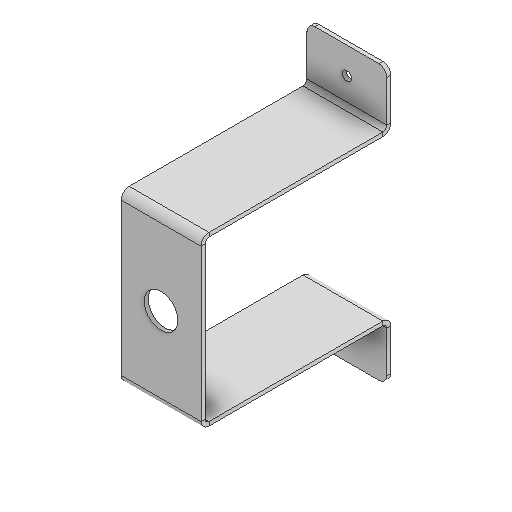
# Autodesk Inventor part: CHAPA 16 DE ACO INOX-304 - SUPORTE CHAVE AUTO-MANUAL
Saved by Autodesk Inventor 2022.2 (Build 262287010, 287A)
## iProperties
Created: 2022-01-21
Part Number: CHAPA 16 DE ACO INOX-304 - SUPORTE CHAVE AUTO-MANUAL
Material: Genérico
Document SubType Name: Sheet Metal
Designer: Projeto
Density: 1 g/cm^3
Flat Pattern Width: 3 cm
Flat Pattern Length: 23.8172 cm
Flat Pattern Area: 71.4515 cm^2
Sheet Metal Rule: Padrão_mm
Sheet Metal Width: 30,000 mm
Sheet Metal Length: 238,172 mm
Sheet Metal Area: 7145,150 mm^2
Appearance: Padrão
Mass: 10.5127 g
Surface Area: 149.083 cm^2
Volume: 10.5127 cm^3
Author: Projeto
Autodesk Inventor part; units mm, degrees
ref_plane "YZ Plane" through (0, 0, 0) normal (1, 0, 0) x (0, 1, 0)
ref_plane "XZ Plane" through (0, 0, 0) normal (0, 1, 0) x (-1, 0, 0)
ref_plane "XY Plane" through (0, 0, 0) normal (0, 0, 1) x (1, 0, 0)
sketch "Esboço1" plane through (0, 0, 0) normal (0, 0, 1) x (1, 0, 0)
  line L0 (15, -30) -> (-15, -30)
  line L1 (-15, -30) -> (-15, 30)
  line L2 (-15, 30) -> (15, 30)
  line L3 (15, 30) -> (15, -30)
  line L4 (15, -30) -> (-15, 30) construction
  line L5 (-15, -30) -> (15, 30) construction
  point P0 (0, 0)
  dimension "d0" = 30
  dimension "d1" = 60
  measures "d0" distance of L1.end L2.end
  measures "d1" distance of L0.end L1.end
extrude "Placa1" add sketch "Esboço1" along normal blind 1.5
sketch "Esboço2" plane through (15, 30, 0) normal (0, 1, 0) x (-1, 0, 0)
  line L0 (30, 0) -> (0, 0)
  line L1 (0, 0) -> (0, -68.3)
  line L2 (0, -68.3) -> (30, -68.3)
  line L3 (30, -68.3) -> (30, 0)
  constraints: 6 end point, 1 horizontal, 1 perpendicular, 1 vertical
edge flange "Flange1" height 68.3 angle 90 thickness 1.5 bend radius 1.5 thickness toward (0, 1, 0) relief tear relief width 1.5 relief depth 0.75 corner gap 1.5 corner form 0 edges at (0, 30, 0) (0, -30, 0) wall of the first edge with corners at (-15, 30, 0) (15, 30, 0) (15, 30, -68.3) (-15, 30, -68.3)
bend "Vergadura1"
corner "Canto1"
sketch "Esboço3" plane through (-15, 31.5, -68.3) normal (0, 0, -1) x (-1, 0, 0)
  line L0 (-30, 0) -> (0, 0)
  line L1 (0, 0) -> (0, 20)
  line L2 (0, 20) -> (-30, 20)
  line L3 (-30, 20) -> (-30, 0)
  constraints: 6 end point, 1 horizontal, 1 perpendicular, 1 vertical
edge flange "Flange2" height 20 angle 90 thickness 1.5 bend radius 1.5 thickness toward (0, 0, -1) relief tear relief width 1.5 relief depth 0.75 corner gap 1.5 corner form 0 edges at (0, 31.5, -68.3) (0, -31.5, -68.3) wall of the first edge with corners at (15, 31.5, -68.3) (-15, 31.5, -68.3) (-15, 51.5, -68.3) (15, 51.5, -68.3)
bend "Vergadura2"
corner "Canto2"
sketch "Esboço4" plane through (15, 51.5, -69.8) normal (0, 0, -1) x (-1, 0, 0)
  line L0 (0, 0) -> (30, 0) projected
  line L1 (30, -103) -> (0, -103) projected
  point P0 (15, -51.5)
  point P1 (15, -10)
  point P2 (15, -93)
  dimension "d23" = 10
  dimension "d24" = 10
  constraints: 2 vertical alignment
  measures "d23" distance from line of point (15, -10) L0
  measures "d24" distance from line of point (15, -93) L1
hole "Furo1" at (0, 41.5, -69.8) at (0, -41.5, -69.8) direction (0, 0, 1) diameter 3.5 depth 1.5 tip angle 118
sketch "Esboço5" plane through (0, 0, 1.5) normal (0, 0, 1) x (1, 0, 0)
  point P0 (0, 0)
  point P1 (0, 0)
  constraints: 1 coincident
hole "Furo2" at (0, 0, 1.5) direction (0, 0, -1) diameter 12.7 depth 1.5 tip angle 118
fillet "Arredondamento de canto1" radius 3 4 edges at (15, 51.5, -69.05) (-15, 51.5, -69.05) (15, -51.5, -69.05) (-15, -51.5, -69.05)
equation "\"d30\" = Espessura"
equation "\"d37\" = Espessura"
equation "\"d2\" = Espessura"
equation "\"d3\" = Largura_alívio_de_vergadura"
equation "\"d4\" = Profundidade_alívio_de_vergadura"
equation "\"d5\" = Remanescente_mínimo"
equation "\"d6\" = Raiodetransição"
equation "\"d9\" = Raio_vergadura"
equation "\"d10\" = Tamanho_alívio_de_dobra"
equation "\"d11\" = TamanhoFolga"
equation "\"d12\" = Tamanho_de_raio_de_Jacobi"
equation "\"d13\" = Largura_alívio_de_vergadura"
equation "\"d14\" = Profundidade_alívio_de_vergadura"
equation "\"d15\" = Remanescente_mínimo"
equation "\"d16\" = Raiodetransição"
equation "\"d19\" = Raio_vergadura"
equation "\"d20\" = Tamanho_alívio_de_dobra"
equation "\"d21\" = TamanhoFolga"
equation "\"d22\" = Tamanho_de_raio_de_Jacobi"
equation "\"Raio_vergadura\" = Espessura"
equation "\"Largura_alívio_de_vergadura\" = Espessura"
equation "\"Profundidade_alívio_de_vergadura\" = 0.5 * Espessura"
equation "\"Tamanho_alívio_de_dobra\" = 4 * Espessura"
equation "\"Remanescente_mínimo\" = 2 * Espessura"
equation "\"Raiodetransição\" = Raio_vergadura"
equation "\"Tamanho_de_raio_de_Jacobi\" = Raio_vergadura"
equation "\"TamanhoFolga\" = Espessura"
equation "\"Espessura\" = 1.5"
